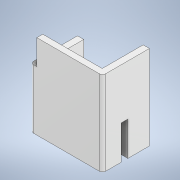
# Autodesk Inventor part: Tapa_meta_indice
Saved by Autodesk Inventor 2021 (Build 250183000, 183)
## iProperties
Created: 2026-04-06
Part Number: Tapa_meta_indice
Material: Plástico ABS
Document SubType Name: Modeling
Designer: thepr
Density: 1 g/cm^3
Appearance: Suave - Blanco
Author: thepr
## iProperties of the stored document _3DPrint.ipt
Created: 2026-05-08
Part Number: _3DPrint
Material: Genérico
Document SubType Name: Modeling
Designer: thepr
Density: 1 g/cm^3
Appearance: Valor por defecto
Author: thepr
Autodesk Inventor part; units mm, degrees
ref_plane "YZ Plane" through (0, 0, 0) normal (1, 0, 0) x (0, 1, 0)
ref_plane "XZ Plane" through (0, 0, 0) normal (0, 1, 0) x (-1, 0, 0)
ref_plane "XY Plane" through (0, 0, 0) normal (0, 0, 1) x (1, 0, 0)
sketch "Boceto1" plane through (0, 0, 0) normal (0, 0, 1) x (1, 0, 0)
  line L0 (0, 0) -> (23, 0)
  line L1 (23, 0) -> (23, 28)
  line L2 (23, 28) -> (0, 28)
  line L3 (0, 28) -> (0, 0)
  dimension "d0" = 23
  dimension "d1" = 28
  constraints: 8 end point, 2 parallel, 1 horizontal, 1 perpendicular
  measures "d0" distance between parallel lines of L1 L3
  measures "d1" distance of L2.end L0.start
extrude "Extrusión1" add sketch "Boceto1" along normal blind 2
sketch "Boceto2" plane through (0, 0, 0) normal (0, 0, -1) x (-1, 0, 0)
  line L0 (-23, 0) -> (-23, 28) projected
  line L1 (0, 0) -> (-23, 0) projected
  line L2 (0, 28) -> (0, 0) projected
  line L3 (-23, 28) -> (0, 28) projected
  line L4 (-23, 28) -> (0, 28) projected
  line L5 (-21, 28) -> (-21, 0)
  line L6 (-2, 28) -> (-2, 0)
  point P0 (-2, 28)
  dimension "d4" = 2
  dimension "d5" = 2
  constraints: 4 end point, 4 point on line, 2 perpendicular
  measures "d4" distance between parallel lines of L2 L6
  measures "d5" distance between parallel lines of L0 L5
extrude "Extrusión2" add sketch "Boceto2" along normal blind 13 contours L0 L3 L5 L1 | L6 L3 L2 L1
fillet "Empalme1" radius 4 2 edges at (0, 14, 2) (23, 14, 2)
sketch "Boceto3" plane through (23, 0, -13) normal (1, 0, 0) x (0, 0, -1)
  circle A0 centre (-5, 14) radius 2.5
  line L0 (0, 28) -> (0, 0) projected
  line L1 (-11, 0) -> (0, 0) projected
  line L2 (-5, 16.5) -> (0, 16.5)
  line L3 (-5, 11.5) -> (0, 11.5)
  point P0 (-13, 0)
  dimension "d9" = 5
  dimension "d10" = 5
  dimension "d11" = 14
  constraints: 4 end point, 2 point on circle, 2 point on line, 2 tangent, 1 centre point, 1 parallel, 1 perpendicular
  measures "d9" diameter of A0
  measures "d10" distance from line of L0 A0.centre
  measures "d11" distance from line of L1 A0.centre
extrude "Extrusión3" [suppressed]
sketch "Boceto4" plane through (0, 0, 0) normal (0, 0, -1) x (-1, 0, 0)
  line L0 (-19, 28) -> (-19, 0) projected
  line L1 (-4, 0) -> (-4, 28) projected
  line L2 (-21, 28) -> (-2, 28) projected
  line L3 (-2, 0) -> (-21, 0) projected
  line L4 (-16, 28) -> (-16, 0)
  line L5 (-6, 28) -> (-6, 0)
  line L6 (-4, 0) -> (-19, 0) projected
  point P0 (0, 0)
  dimension "d14" = 10
  dimension "d15" = 3
  constraints: 4 end point, 4 point on line, 1 parallel, 1 perpendicular
  measures "d14" distance between parallel lines of L4 L5
  measures "d15" distance between parallel lines of L4 L0
extrude "Extrusión4" add sketch "Boceto4" along normal blind 2 contours L2 L5 L3 L4
move faces "Desplazar1" translate (0, 0, -0.5) faces at (12.6667, 18.6667, -2)
sketch "Boceto5" plane through (0, 0, -13) normal (-1, 0, 0) x (0, 0, 1)
  line L0 (13, 0) -> (0, 0) projected
  line L1 (7, 0) -> (9, 0)
  line L2 (9, 0) -> (9, 10)
  line L3 (9, 10) -> (7, 10)
  line L4 (7, 10) -> (7, 0)
  point P0 (13, 28)
  dimension "d23" = 4
  dimension "d24" = 2
  dimension "d25" = 10
  constraints: 8 end point, 2 parallel, 1 horizontal, 1 perpendicular, 1 point on line
  measures "d23" distance from line of point (13, 28) L2
  measures "d24" distance between parallel lines of L2 L4
  measures "d25" distance between parallel lines of L3 L0
extrude "Extrusión5" cut sketch "Boceto5" against normal blind 40
sketch "Boceto6" plane through (21, 28, -13) normal (0, 1, 0) x (1, 0, 0)
  arc A0 (-2, -15) -> (2, -11) centre (-2, -11) ccw projected
  line L0 (2, 0) -> (2, -11) projected
  line L1 (0, 0) -> (2, 0) projected
  line L2 (0, -13) -> (0, 0) projected
  line L3 (0, -13) -> (-5, -13) projected
  line L4 (-5, -13) -> (-5, -10.5) projected
  line L5 (-15, -10.5) -> (-5, -10.5) projected
  line L6 (-15, -13) -> (-15, -10.5) projected
  line L7 (-15, -13) -> (-19, -13) projected
  line L8 (-19, -13) -> (-19, 0) projected
  line L9 (-21, 0) -> (-19, 0) projected
  line L10 (-21, 0) -> (-21, -11) projected
  arc A1 (-21, -11) -> (-17, -15) centre (-17, -11) ccw projected
  line L11 (-2, -15) -> (-17, -15) projected
  point P0 (-21, -13)
extrude "Extrusión6" cut sketch "Boceto6" against normal blind 9
sketch "Boceto7" plane through (0, 0, 0) normal (0, 0, -1) x (-1, 0, 0)
  line L0 (-16, 19) -> (-21, 19) projected
  line L1 (-21, 19) -> (-21, 0) projected
  line L2 (-16, 0) -> (-21, 0) projected
  line L3 (-16, 0) -> (-16, 19) projected
  line L4 (-2, 19) -> (-6, 19) projected
  line L5 (-6, 19) -> (-6, 0) projected
  line L6 (-2, 0) -> (-6, 0) projected
  line L7 (-2, 0) -> (-2, 19) projected
  point P0 (0, 0)
extrude "Extrusión7" add sketch "Boceto7" along normal up to surface (2.5 mm away)
sketch "Boceto8" plane through (21, 0, -2.5) normal (0, 0, -1) x (-1, 0, 0)
  line L0 (0, 19) -> (19, 19) projected
  line L1 (0, 0) -> (0, 19) projected
  line L2 (19, 0) -> (0, 0) projected
  line L3 (19, 19) -> (19, 0) projected
  line L4 (17, 0) -> (2, 0) projected
  line L5 (2.6, 0) -> (2.6, 19)
  line L6 (16.4, 0) -> (16.4, 19)
  point P0 (21, 0)
  dimension "d32" = 2.6
  dimension "d33" = 2.6
  constraints: 4 end point, 4 point on line, 1 parallel, 1 perpendicular
  measures "d32" distance between parallel lines of L3 L6
  measures "d33" distance between parallel lines of L5 L1
extrude "Extrusión8" cut sketch "Boceto8" against normal blind 2.6 contours L0 L5 L2 L1 | L0 L3 L2 L6
move faces "Desplazar2" translate (0, 0, -0.1) faces at (13.8, 12.6667, -2.5)
move faces "Desplazar3" translate (0, 0.9, 0) faces at (0.6667, 10, -4.6667) (22.3333, 10, -5.3333)
sketch "Boceto9" plane through (21, 19, -13) normal (0, 1, 0) x (1, 0, 0)
  line L0 (0, -13.1) -> (0, 0) projected
  line L1 (0, -13.1) -> (-2.6, -13.1) projected
  line L2 (-2.6, -13.1) -> (-2.6, -10.4) projected
  line L3 (-2.6, -10.4) -> (-16.4, -10.4) projected
  line L4 (-16.4, -10.4) -> (-16.4, -13.1) projected
  line L5 (-16.4, -13.1) -> (-19, -13.1) projected
  line L6 (-19, 0) -> (-19, -13.1) projected
  line L7 (-21, 0) -> (-19, 0) projected
  line L8 (-21, -11) -> (-21, 0) projected
  arc A0 (-21, -11) -> (-17, -15) centre (-17, -11) ccw projected
  line L9 (-2, -15) -> (-17, -15) projected
  arc A1 (-2, -15) -> (2, -11) centre (-2, -11) ccw projected
  line L10 (2, 0) -> (2, -11) projected
  line L11 (0, 0) -> (2, 0) projected
  line L12 (-19, -13.1) -> (-19, -14.4641)
  arc A2 (-21, -11) -> (-17, -15) centre (-17, -11) ccw projected
  line L13 (-16.4, -13.1) -> (-2.6, -13.1)
  point P0 (-21, -13)
  constraints: 4 end point, 1 perpendicular, 1 point on circle, 1 vertical
extrude "Extrusión9" add sketch "Boceto9" along normal blind 8 contours L0 L11 L10 A1 L9 A0 L12 L5 L13 L1
sketch "Boceto10" plane through (0, 0, 2) normal (0, 0, 1) x (1, 0, 0)
  line L0 (4, 0) -> (4, 27) projected
  line L1 (4, 0) -> (19, 0) projected
  line L2 (19, 27) -> (19, 0) projected
  line L3 (4, 27) -> (19, 27) projected
  line L4 (23, 0) -> (23, 27) projected
  line L5 (0, 19) -> (0, 0) projected
  line L6 (2, 19) -> (2, 0) projected
  line L7 (2, 19) -> (0, 19) projected
  line L8 (0, 19) -> (0, 0) projected
  line L9 (0, 0) -> (4, 0) projected
  line L10 (4, 0) -> (4, 27) projected
  line L11 (2, 27) -> (4, 27) projected
  line L12 (2, 19) -> (2, 27) projected
  line L13 (21, 0) -> (21, 27) projected
  line L14 (19, 27) -> (19, 0) projected
  line L15 (19, 0) -> (23, 0) projected
  line L16 (23, 0) -> (23, 27) projected
  line L17 (19, 27) -> (23, 27) projected
extrude "Extrusión10" add sketch "Boceto10" against normal blind 4 contours L9 L5 L7 L6 | L13 L17 L4 L15
extrude "Extrusión11" add sketch "Boceto10" against normal blind 1 contours L9 L6 L12 L11 L0 | L2 L17 L13 L15
move faces "Desplazar4" translate (0, 0, -0.1) faces at (1.3333, 7.2667, -6) (21.6667, 7.2667, -6)
fillet "Empalme2" radius 1 2 edges at (23, 13.5, 2) (0, 9.5, 2)
